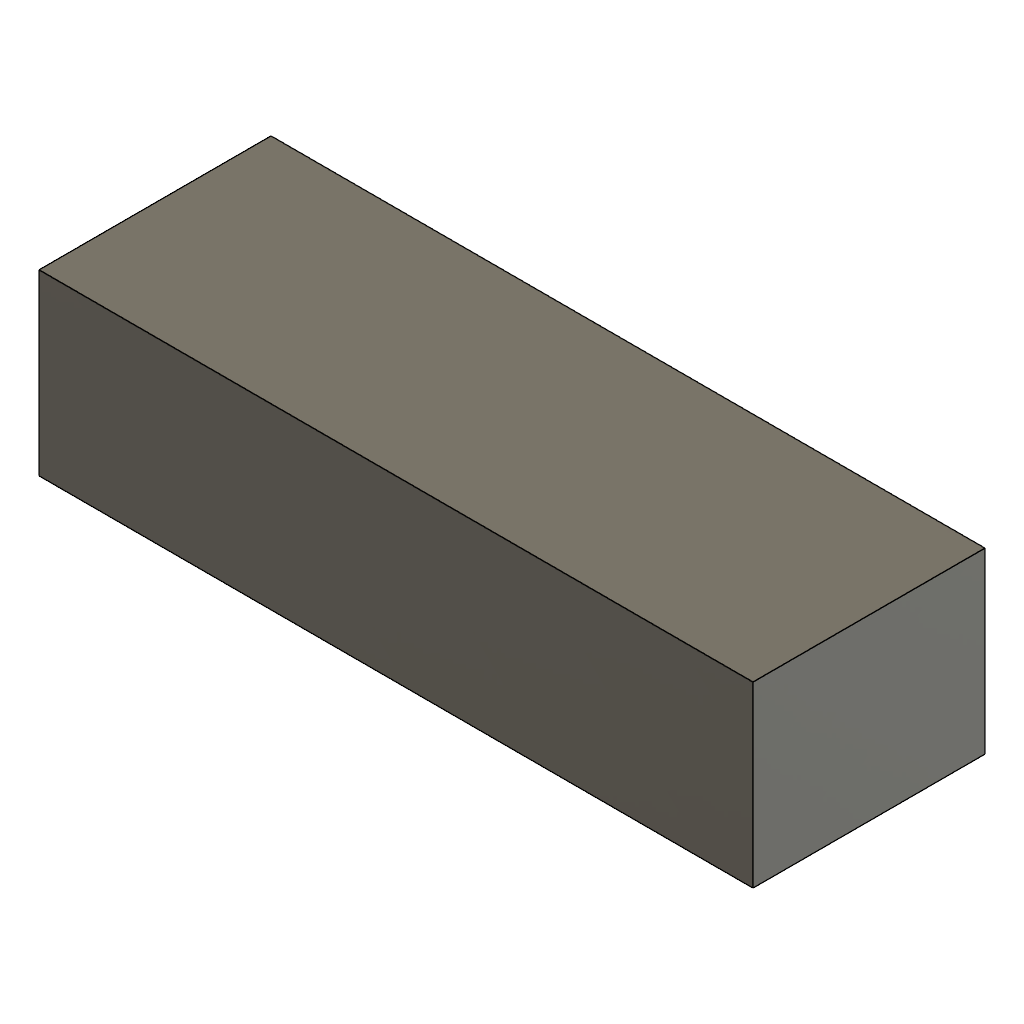
variation (Autodesk Fusion 360 design; units mm, degrees)
part number: 2026-11-22-19-18-14-432
Autodesk Fusion 360 part; units mm, degrees
sketch "Sketch1" plane through (0, 0, 0) normal (0, 1, 0) x (1, 0, 0)
  line L0 (0, 0) -> (40, 0)
  line L1 (40, 0) -> (40, 13)
  line L2 (40, 13) -> (0, 13)
  line L3 (0, 13) -> (0, 0)
extrude "ControlledBoss" add sketch "Sketch1" against normal blind 10
